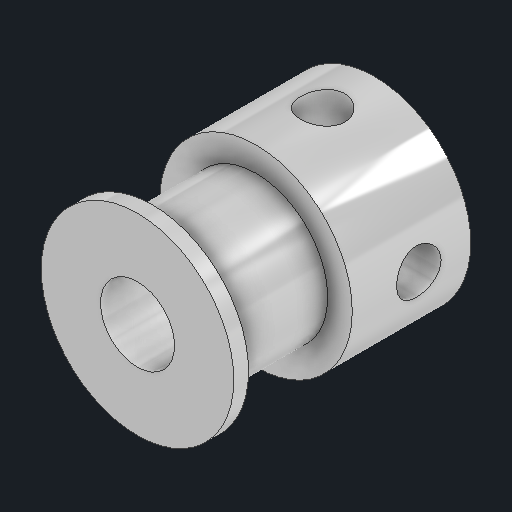
# Autodesk Inventor part: gt2_16T_bore5
Saved by Autodesk Inventor 2027.1 (Build 311270010, 270A)
## iProperties
Created: 2026-11-04
Part Number: gt2_16T_bore5
Material: Generic
Description: GT2 16T pulley, 6 mm belt, 5 mm bore, hub 13 x 7 with 2x M3 grub
Document SubType Name: Modeling
Designer: Claude (from photos)
Density: 1 g/cm^3
Appearance: Aluminum - Polished
Author: alexg
Autodesk Inventor part; units mm, degrees
ref_plane "YZ Plane" through (0, 0, 0) normal (1, 0, 0) x (0, 1, 0)
ref_plane "XZ Plane" through (0, 0, 0) normal (0, 1, 0) x (-1, 0, 0)
ref_plane "XY Plane" through (0, 0, 0) normal (0, 0, 1) x (1, 0, 0)
sketch "Pulley body sketch" plane through (0, 0, 0) normal (1, 0, 0) x (0, 1, 0)
  line L0 (2.5, 0) -> (2.5, 16)
  line L1 (2.5, 16) -> (6.5, 16)
  line L2 (6.5, 16) -> (6.5, 15)
  line L3 (6.5, 15) -> (4.84, 15)
  line L4 (4.84, 15) -> (4.84, 8)
  line L5 (4.84, 8) -> (6.5, 8)
  line L6 (6.5, 8) -> (6.5, 7)
  line L7 (6.5, 7) -> (6.5, 0)
  line L8 (6.5, 0) -> (2.5, 0)
  line L9 (0, -3.2) -> (0, 19.2) projected
  constraints: 18 end point
revolve "Pulley body" add sketch "Pulley body sketch" angle 360 about axis through (0, 0, -10) along (0, 0, 1)
sketch "Grub M3 #1 sketch" plane through (0, 0, 0) normal (0, 1, 0) x (-1, 0, 0)
  circle A0 centre (0, 3.5) radius 1.5
  constraints: 1 centre point
extrude "Grub M3 #1" cut sketch "Grub M3 #1 sketch" along normal blind 12
sketch "Grub M3 #2 sketch" plane through (0, 0, 0) normal (1, 0, 0) x (0, 1, 0)
  circle A0 centre (0, 3.5) radius 1.5
  constraints: 1 centre point
extrude "Grub M3 #2" cut sketch "Grub M3 #2 sketch" along normal blind 12
body "Solid1"
